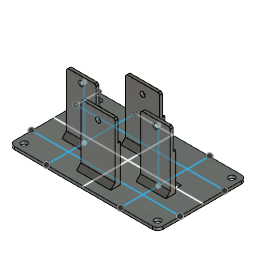
Chargers mount (Autodesk Fusion 360 design; units mm, degrees)
Autodesk Fusion 360 part; units mm, degrees
sketch "Sketch1" plane through (0, 0, 0) normal (0, 0, 1) x (1, 0, 0)
  line L0 (0, 0) -> (100, 0)
  line L1 (100, 0) -> (100, 60)
  line L2 (100, 60) -> (0, 60)
  line L3 (0, 60) -> (0, 0)
  dimension "d1" = 100
  dimension "d2" = 60
  constraint horizontal L0
  constraint vertical L1
  constraint horizontal L2
  constraint vertical L3
  constraint coincident L0.start L3.end
  measures "d1" distance of L0.start L0.end
  measures "d2" distance of L0.start L2.end
extrude "Extrude1" add sketch "Sketch1" along normal blind 2
sketch "Sketch2" plane through (0, 0, 2) normal (0, 0, 1) x (-1, 0, 0)
  line L0 (0, -60) -> (0, 0)
  line L1 (0, 0) -> (-100, 0)
  line L2 (-100, 0) -> (-100, -60)
  line L3 (-100, -60) -> (0, -60)
  line L4 (-50, -60) -> (-50, 0)
  line L5 (0, -30) -> (-100, -30)
  line L6 (-95, -5) -> (-5, -5)
  line L7 (-5, -5) -> (-5, -55)
  line L8 (-5, -55) -> (-95, -55)
  line L9 (-95, -55) -> (-95, -5)
  line L10 (-95, -5) -> (-5, -55) construction
  line L11 (-5, -5) -> (-95, -55) construction
  circle A0 centre (-5, -55) radius 2.1
  circle A1 centre (-95, -55) radius 2.1
  circle A2 centre (-5, -5) radius 2.1
  circle A3 centre (-95, -5) radius 2.1
  point P0 (-50, -30)
  dimension "d5" = 4.2
  dimension "d6" = 4.2
  dimension "d7" = 4.2
  dimension "d8" = 4.2
  constraint midpoint L3 L4.start
  constraint perpendicular L3 L4
  constraint midpoint L0 L5.start
  constraint perpendicular L4 L5
  constraint horizontal L6
  constraint perpendicular L6 L7
  constraint parallel L6 L8
  constraint parallel L7 L9
  constraint coincident L10 P0
  constraint coincident L11 P0
  constraint midpoint L4 P0
  constraint coincident L7.end L8.start
  constraint coincident L8.end L9.start
  constraint coincident L6.end L7.start
  constraint coincident L6.start L9.end
  measures "d5" diameter of A0
  measures "d6" diameter of A1
  measures "d7" diameter of A2
  measures "d8" diameter of A3
extrude "Extrude2" cut sketch "Sketch2" against normal blind 2345 contours L6 L7 A2 | L6 L7 A2 | L7 L8 A0 | L7 L8 A0 | L8 L9 A1 | L8 L9 A1 | L6 L9 A3 | L6 L9 A3
sketch "Sketch3" plane through (0, 0, 2) normal (0, 0, 1) x (-1, 0, 0)
  circle A0 centre (-95, -55) radius 2.1
  circle A1 centre (-95, -5) radius 2.1
  circle A2 centre (-5, -55) radius 2.1
  circle A3 centre (-5, -5) radius 2.1
  line L0 (0, -60) -> (0, 0)
  line L1 (0, 0) -> (-100, 0)
  line L2 (-100, 0) -> (-100, -60)
  line L3 (-100, -60) -> (0, -60)
  line L4 (-50, -60) -> (-50, 0)
  line L5 (0, -30) -> (-100, -30)
  line L6 (0, -60) -> (0, -45)
  line L7 (0, -45) -> (-100, -45)
  line L8 (-100, -15) -> (0, -15)
  line L9 (-50, -60) -> (-25, -60)
  line L10 (-25, -60) -> (-25, 0)
  line L11 (-75, -60) -> (-75, 0)
  constraint midpoint L3 L4.start
  constraint midpoint L1 L4.end
  constraint midpoint L0 L5.start
  constraint midpoint L2 L5.end
  constraint coincident L0.start L3.end
  constraint coincident L0 L6.end
  constraint coincident L2 L7.end
  constraint perpendicular L2 L7
  constraint coincident L2 L8.start
  constraint coincident L0 L8.end
  constraint perpendicular L0 L8
  constraint coincident L3 L9.end
  constraint coincident L1 L10.end
  constraint perpendicular L1 L10
  constraint coincident L3 L11.start
  constraint coincident L1 L11.end
  constraint perpendicular L1 L11
sketch "Sketch4" plane through (0, 0, 2) normal (0, 0, 1) x (-1, 0, 0)
  line L0 (-32.5, -26.5) -> (-17.5, -26.5)
  line L1 (-17.5, -26.5) -> (-17.5, -33.5)
  line L2 (-17.5, -33.5) -> (-32.5, -33.5)
  line L3 (-32.5, -33.5) -> (-32.5, -26.5)
  line L4 (-32.5, -26.5) -> (-17.5, -33.5) construction
  line L5 (-17.5, -26.5) -> (-32.5, -33.5) construction
  line L6 (-82.5, -26.5) -> (-67.5, -26.5)
  line L7 (-67.5, -26.5) -> (-67.5, -33.5)
  line L8 (-67.5, -33.5) -> (-82.5, -33.5)
  line L9 (-82.5, -33.5) -> (-82.5, -26.5)
  line L10 (-82.5, -26.5) -> (-67.5, -33.5) construction
  line L11 (-67.5, -26.5) -> (-82.5, -33.5) construction
  point P0 (-25, -30)
  point P1 (-75, -30)
  dimension "d11" = 15
  dimension "d12" = 7
  dimension "d13" = 15
  dimension "d14" = 7
  constraint horizontal L0
  constraint perpendicular L0 L1
  constraint parallel L0 L2
  constraint parallel L1 L3
  constraint coincident L4 P0
  constraint coincident L5 P0
  constraint horizontal L6
  constraint perpendicular L6 L7
  constraint parallel L6 L8
  constraint parallel L7 L9
  constraint coincident L10 P1
  constraint coincident L11 P1
  measures "d11" distance of L1.end L2.end
  measures "d12" distance of L0.end L1.end
  measures "d13" distance of L7.end L8.end
  measures "d14" distance of L6.end L7.end
sketch "Sketch5" plane through (0, 0, 2) normal (0, 0, 1) x (-1, 0, 0)
  line L0 (-45, -13.2) -> (-55, -13.2)
  arc A0 (-55, -13.2) -> (-55, -16.8) centre (-55, -15) ccw
  line L1 (-55, -16.8) -> (-45, -16.8)
  arc A1 (-45, -16.8) -> (-45, -13.2) centre (-45, -15) ccw
  line L2 (-45, -15) -> (-55, -15) construction
  line L3 (-45, -43.2) -> (-55, -43.2)
  arc A2 (-55, -43.2) -> (-55, -46.8) centre (-55, -45) ccw
  line L4 (-55, -46.8) -> (-45, -46.8)
  arc A3 (-45, -46.8) -> (-45, -43.2) centre (-45, -45) ccw
  line L5 (-45, -45) -> (-55, -45) construction
  point P0 (-50, -15)
  point P1 (-50, -45)
  dimension "d15" = 5
  dimension "d16" = 3.6
  dimension "d17" = 5
  dimension "d18" = 3.6
  constraint tangent L0 A0
  constraint tangent A0 L1
  constraint parallel L0 L1
  constraint tangent L1 A1
  constraint tangent L0 A1
  constraint horizontal L2
  constraint midpoint L2 P0
  constraint tangent L3 A2
  constraint tangent A2 L4
  constraint parallel L3 L4
  constraint tangent L4 A3
  constraint tangent L3 A3
  constraint horizontal L5
  constraint midpoint L5 P1
  measures "d15" distance of A0.centre P0
  measures "d16" diameter of A0
  measures "d17" distance of A2.centre P1
  measures "d18" diameter of A2
extrude "Extrude3" cut sketch "Sketch4" sketch "Sketch5" against normal blind 346436 of sketch 2
sketch "Sketch6" plane through (0, 0, 0) normal (0, 0, -1) x (1, 0, 0)
  line L0 (0, 0) -> (0, -60)
  line L1 (0, -60) -> (100, -60)
  line L2 (100, -60) -> (100, 0)
  line L3 (100, 0) -> (0, 0)
  circle A0 centre (5, -5) radius 2.1
  circle A1 centre (5, -55) radius 2.1
  circle A2 centre (95, -5) radius 2.1
  circle A3 centre (95, -55) radius 2.1
  line L4 (45, -13.2) -> (55, -13.2)
  arc A4 (55, -16.8) -> (55, -13.2) centre (55, -15) ccw
  line L5 (55, -16.8) -> (45, -16.8)
  arc A5 (45, -13.2) -> (45, -16.8) centre (45, -15) ccw
  line L6 (67.5, -33.5) -> (67.5, -26.5)
  line L7 (67.5, -26.5) -> (82.5, -26.5)
  line L8 (82.5, -26.5) -> (82.5, -33.5)
  line L9 (82.5, -33.5) -> (67.5, -33.5)
  line L10 (17.5, -33.5) -> (17.5, -26.5)
  line L11 (17.5, -26.5) -> (32.5, -26.5)
  line L12 (32.5, -26.5) -> (32.5, -33.5)
  line L13 (32.5, -33.5) -> (17.5, -33.5)
  line L14 (45, -43.2) -> (55, -43.2)
  arc A6 (55, -46.8) -> (55, -43.2) centre (55, -45) ccw
  line L15 (55, -46.8) -> (45, -46.8)
  arc A7 (45, -43.2) -> (45, -46.8) centre (45, -45) ccw
  line L16 (75, -50) -> (25, -50) construction
  line L17 (25, -50) -> (25, -60) construction
  line L18 (25, -60) -> (75, -60) construction
  line L19 (75, -60) -> (75, -50) construction
  line L20 (57, -37) -> (43, -37) construction
  line L21 (43, -37) -> (43, -42) construction
  line L22 (43, -42) -> (57, -42) construction
  line L23 (57, -42) -> (57, -37) construction
  line L24 (57, -18) -> (43, -18) construction
  line L25 (43, -18) -> (43, -23) construction
  line L26 (43, -23) -> (57, -23) construction
  line L27 (57, -23) -> (57, -18) construction
  line L28 (83, -20) -> (67, -20) construction
  line L29 (67, -20) -> (67, -25) construction
  line L30 (67, -25) -> (83, -25) construction
  line L31 (83, -25) -> (83, -20) construction
  line L32 (33, -20) -> (17, -20) construction
  line L33 (17, -20) -> (17, -25) construction
  line L34 (17, -25) -> (33, -25) construction
  line L35 (33, -25) -> (33, -20) construction
  dimension "d21" = 5.76
  dimension "d23" = 4
  dimension "d24" = 0
  dimension "d25" = 4
  dimension "d26" = 0
  dimension "d27" = 4
  dimension "d28" = 0
  dimension "d29" = 4
  dimension "d30" = 0
  text T0 "Chargers" font "Arial" height 5.76 align centre middle in box 50 x 10 at (75, -50) x (-1, 0) y (0, -1) spacing 1 kerned
  text T1 "65 W" font "Arial" height 4 align centre middle in box 14 x 5 at (57, -37) x (-1, 0) y (0, -1) spacing 1 kerned
  text T2 "65 W" font "Arial" height 4 align centre middle in box 14 x 5 at (57, -18) x (-1, 0) y (0, -1) spacing 1 kerned
  text T3 "24 W" font "Arial" height 4 align centre middle in box 16 x 5 at (83, -20) x (-1, 0) y (0, -1) spacing 1 kerned
  text T4 "24 W" font "Arial" height 4 align centre middle in box 16 x 5 at (33, -20) x (-1, 0) y (0, -1) spacing 1 kerned
  constraint coincident L1
extrude "Extrude4" cut sketch "Sketch6" against normal blind 0.5 text T0 T1 T3 T2 T4
sketch "Sketch7" plane through (0, 0, 2) normal (0, 0, 1) x (-1, 0, 0)
  line L0 (-45, -43) -> (-55, -43)
  arc A0 (-55, -43) -> (-55, -47) centre (-55, -45) ccw
  line L1 (-55, -47) -> (-45, -47)
  arc A1 (-45, -47) -> (-45, -43) centre (-45, -45) ccw
  line L2 (-45, -45) -> (-55, -45) construction
  line L3 (-45, -13) -> (-55, -13)
  arc A2 (-55, -13) -> (-55, -17) centre (-55, -15) ccw
  line L4 (-55, -17) -> (-45, -17)
  arc A3 (-45, -17) -> (-45, -13) centre (-45, -15) ccw
  line L5 (-45, -15) -> (-55, -15) construction
  point P0 (-50, -45)
  point P1 (-50, -15)
  dimension "d33" = 4
  dimension "d34" = 5
  dimension "d35" = 4
  constraint tangent L0 A0
  constraint tangent A0 L1
  constraint parallel L0 L1
  constraint tangent L1 A1
  constraint tangent L0 A1
  constraint horizontal L2
  constraint midpoint L2 P0
  constraint tangent L3 A2
  constraint tangent A2 L4
  constraint parallel L3 L4
  constraint tangent L4 A3
  constraint tangent L3 A3
  constraint parallel L2 L5
  constraint midpoint L5 P1
  measures "d33" diameter of A0
  measures "d34" distance of A2.centre P1
  measures "d35" diameter of A2
extrude "Extrude5" cut sketch "Sketch7" against normal blind 6543
sketch "Sketch8" plane through (0, 0, 2) normal (0, 0, 1) x (-1, 0, 0)
  line L0 (-50, -43) -> (-50, -42.4)
  line L1 (-60.5, -41.8) -> (-39.5, -41.8)
  line L2 (-39.5, -41.8) -> (-39.5, -43)
  line L3 (-39.5, -43) -> (-60.5, -43)
  line L4 (-60.5, -43) -> (-60.5, -41.8)
  line L5 (-60.5, -41.8) -> (-39.5, -43) construction
  line L6 (-39.5, -41.8) -> (-60.5, -43) construction
  line L7 (-50, -13) -> (-50, -12.4)
  line L8 (-60.5, -11.8) -> (-39.5, -11.8)
  line L9 (-39.5, -11.8) -> (-39.5, -13)
  line L10 (-39.5, -13) -> (-60.5, -13)
  line L11 (-60.5, -13) -> (-60.5, -11.8)
  line L12 (-60.5, -11.8) -> (-39.5, -13) construction
  line L13 (-39.5, -11.8) -> (-60.5, -13) construction
  line L14 (-25, -26.5) -> (-25, -26)
  line L15 (-34, -26.5) -> (-16, -26.5)
  line L16 (-16, -26.5) -> (-16, -25.5)
  line L17 (-16, -25.5) -> (-34, -25.5)
  line L18 (-34, -25.5) -> (-34, -26.5)
  line L19 (-34, -26.5) -> (-16, -25.5) construction
  line L20 (-16, -26.5) -> (-34, -25.5) construction
  line L21 (-75, -26.5) -> (-75, -26)
  line L22 (-84, -25.5) -> (-66, -25.5)
  line L23 (-66, -25.5) -> (-66, -26.5)
  line L24 (-66, -26.5) -> (-84, -26.5)
  line L25 (-84, -26.5) -> (-84, -25.5)
  line L26 (-84, -25.5) -> (-66, -26.5) construction
  line L27 (-66, -25.5) -> (-84, -26.5) construction
  point P0 (-50, -42.4)
  point P1 (-50, -12.4)
  point P2 (-25, -26)
  point P3 (-75, -26)
  dimension "d38" = 0.6
  dimension "d39" = 21
  dimension "d40" = 1.2
  dimension "d41" = 0.6
  dimension "d42" = 21
  dimension "d43" = 1.2
  dimension "d44" = 0.5
  dimension "d45" = 18
  dimension "d46" = 1
  dimension "d47" = 18
  dimension "d48" = 1
  constraint vertical L0
  constraint horizontal L1
  constraint perpendicular L1 L2
  constraint parallel L1 L3
  constraint parallel L2 L4
  constraint coincident L5 P0
  constraint coincident L6 P0
  constraint coincident P0 L0.end
  constraint vertical L7
  constraint horizontal L8
  constraint perpendicular L8 L9
  constraint parallel L8 L10
  constraint parallel L9 L11
  constraint coincident L12 P1
  constraint coincident L13 P1
  constraint coincident P1 L7.end
  constraint vertical L14
  constraint horizontal L15
  constraint perpendicular L15 L16
  constraint parallel L15 L17
  constraint parallel L16 L18
  constraint coincident L19 P2
  constraint coincident L20 P2
  constraint coincident P2 L14.end
  constraint vertical L21
  constraint horizontal L22
  constraint perpendicular L22 L23
  constraint parallel L22 L24
  constraint parallel L23 L25
  constraint coincident L26 P3
  constraint coincident L27 P3
  constraint coincident P3 L21.end
  measures "d38" distance of L0.start P0
  measures "d39" distance of L2.end L3.end
  measures "d40" distance of L1.end L2.end
  measures "d41" distance of L7.start P1
  measures "d42" distance of L9.end L10.end
  measures "d43" distance of L8.end L9.end
  measures "d44" distance of L14.start P2
  measures "d45" distance of L16.end L17.end
  measures "d46" distance of L15.end L16.end
  measures "d47" distance of L23.end L24.end
  measures "d48" distance of L22.end L23.end
extrude "Extrude6" cut sketch "Sketch8" against normal blind 0.9
sketch "Sketch9" plane through (0, 0, 2) normal (0, 0, 1) x (-1, 0, 0)
  line L0 (-50, -41.8) -> (-50, -40.8)
  line L1 (-50, -11.8) -> (-50, -10.8)
  line L2 (-25, -25.5) -> (-25, -24.5)
  line L3 (-75, -25.5) -> (-75, -24.5)
  line L4 (-61.5, -39.8) -> (-38.5, -39.8)
  line L5 (-38.5, -39.8) -> (-38.5, -41.8)
  line L6 (-38.5, -41.8) -> (-61.5, -41.8)
  line L7 (-61.5, -41.8) -> (-61.5, -39.8)
  line L8 (-61.5, -39.8) -> (-38.5, -41.8) construction
  line L9 (-38.5, -39.8) -> (-61.5, -41.8) construction
  line L10 (-61.5, -9.8) -> (-38.5, -9.8)
  line L11 (-38.5, -9.8) -> (-38.5, -11.8)
  line L12 (-38.5, -11.8) -> (-61.5, -11.8)
  line L13 (-61.5, -11.8) -> (-61.5, -9.8)
  line L14 (-61.5, -9.8) -> (-38.5, -11.8) construction
  line L15 (-38.5, -9.8) -> (-61.5, -11.8) construction
  line L16 (-35, -23.5) -> (-15, -23.5)
  line L17 (-15, -23.5) -> (-15, -25.5)
  line L18 (-15, -25.5) -> (-35, -25.5)
  line L19 (-35, -25.5) -> (-35, -23.5)
  line L20 (-35, -23.5) -> (-15, -25.5) construction
  line L21 (-15, -23.5) -> (-35, -25.5) construction
  line L22 (-85, -23.5) -> (-65, -23.5)
  line L23 (-65, -23.5) -> (-65, -25.5)
  line L24 (-65, -25.5) -> (-85, -25.5)
  line L25 (-85, -25.5) -> (-85, -23.5)
  line L26 (-85, -23.5) -> (-65, -25.5) construction
  line L27 (-65, -23.5) -> (-85, -25.5) construction
  point P0 (-50, -40.8)
  point P1 (-50, -10.8)
  point P2 (-25, -24.5)
  point P3 (-75, -24.5)
  dimension "d51" = 1
  dimension "d52" = 1
  dimension "d53" = 1
  dimension "d54" = 1
  dimension "d55" = 23
  dimension "d56" = 2
  dimension "d57" = 23
  dimension "d58" = 2
  dimension "d59" = 20
  dimension "d60" = 2
  dimension "d61" = 20
  dimension "d62" = 2
  constraint vertical L0
  constraint vertical L1
  constraint vertical L2
  constraint vertical L3
  constraint horizontal L4
  constraint perpendicular L4 L5
  constraint parallel L4 L6
  constraint parallel L5 L7
  constraint coincident L8 P0
  constraint coincident L9 P0
  constraint coincident P0 L0.end
  constraint horizontal L10
  constraint perpendicular L10 L11
  constraint parallel L10 L12
  constraint parallel L11 L13
  constraint coincident L14 P1
  constraint coincident L15 P1
  constraint coincident P1 L1.end
  constraint horizontal L16
  constraint perpendicular L16 L17
  constraint parallel L16 L18
  constraint parallel L17 L19
  constraint coincident L20 P2
  constraint coincident L21 P2
  constraint coincident P2 L2.end
  constraint horizontal L22
  constraint perpendicular L22 L23
  constraint parallel L22 L24
  constraint parallel L23 L25
  constraint coincident L26 P3
  constraint coincident L27 P3
  constraint coincident P3 L3.end
  measures "d51" distance of L0.start P0
  measures "d52" distance of L1.start P1
  measures "d53" distance of L2.start P2
  measures "d54" distance of L3.start P3
  measures "d55" distance of L5.end L6.end
  measures "d56" distance of L4.end L5.end
  measures "d57" distance of L11.end L12.end
  measures "d58" distance of L10.end L11.end
  measures "d59" distance of L17.end L18.end
  measures "d60" distance of L16.end L17.end
  measures "d61" distance of L23.end L24.end
  measures "d62" distance of L22.end L23.end
extrude "Extrude7" add sketch "Sketch9" along normal blind 55
chamfer "Chamfer1" distance 3 angle 45 1 edges at (50, 39.8, 2) tangent chain off
chamfer "Chamfer2" distance 3 angle 45 3 edges at (75, 23.5, 2) (25, 23.5, 2) (50, 9.8, 2) tangent chain off
sketch "Sketch10" plane through (0, 41.8, 0) normal (0, 1, 0) x (-1, 0, 0)
  line L0 (-60.5, 2) -> (-60.5, 1.1)
  line L1 (-60.5, 1.1) -> (-39.5, 1.1)
  line L2 (-39.5, 1.1) -> (-39.5, 2)
  line L3 (-39.5, 2) -> (-38.5, 2)
  line L4 (-38.5, 2) -> (-38.5, 57)
  line L5 (-38.5, 57) -> (-61.5, 57)
  line L6 (-61.5, 57) -> (-61.5, 2)
  line L7 (-61.5, 2) -> (-60.5, 2)
  line L8 (-38.5, 2) -> (-39.5, 2)
  line L9 (-39.5, 2) -> (-39.5, 27)
  line L10 (-39.5, 27) -> (-38.5, 27)
  line L11 (-38.5, 27) -> (-38.5, 2)
  line L12 (-61.5, 2) -> (-60.5, 2)
  line L13 (-60.5, 2) -> (-60.5, 27)
  line L14 (-60.5, 27) -> (-61.5, 27)
  line L15 (-61.5, 27) -> (-61.5, 2)
  dimension "d67" = 1
  dimension "d68" = 25
  dimension "d69" = 1
  dimension "d70" = 25
  constraint horizontal L8
  constraint vertical L9
  constraint horizontal L10
  constraint vertical L11
  constraint coincident L3.end L4.start
  constraint horizontal L12
  constraint vertical L13
  constraint horizontal L14
  constraint vertical L15
  constraint coincident L6.end L7.start
  measures "d67" distance of L3.end L2.end
  measures "d68" distance of L3.end L10.end
  measures "d69" distance of L6.end L0.start
  measures "d70" distance of L6.end L14.end
extrude "Extrude8" add sketch "Sketch10" along normal blind 1.6 contours L6 L7 L12 L13 L14 L15 | L3 L4 L8 L9 L10 L11
sketch "Sketch11" plane through (60.5, 0, 0) normal (-1, 0, 0) x (0, -1, 0)
  line L0 (-43, 2) -> (-43, 1.1)
  line L1 (-43, 1.1) -> (-41.8, 1.1)
  line L2 (-41.8, 1.1) -> (-41.8, 27)
  line L3 (-41.8, 27) -> (-43.4, 27)
  line L4 (-43.4, 27) -> (-43.4, 2)
  line L5 (-43.4, 2) -> (-43, 2)
  line L6 (-43.4, 2) -> (-43, 2)
  line L7 (-43, 2) -> (-43, 9)
  line L8 (-43, 9) -> (-43.4, 9)
  line L9 (-43.4, 9) -> (-43.4, 2)
  dimension "d73" = 0.4
  dimension "d74" = 7
  constraint horizontal L6
  constraint vertical L7
  constraint horizontal L8
  constraint vertical L9
  constraint coincident L4.end L5.start
  measures "d73" distance of L4.end L0.start
  measures "d74" distance of L4.end L8.end
extrude "Extrude9" add sketch "Sketch11" along normal blind 4 contours L4 L5 L6 L7 L8 L9
sketch "Sketch12" plane through (39.5, 0, 0) normal (1, 0, 0) x (0, 1, 0)
  line L0 (41.8, 27) -> (41.8, 1.1)
  line L1 (41.8, 1.1) -> (43, 1.1)
  line L2 (43, 1.1) -> (43, 2)
  line L3 (43, 2) -> (43.4, 2)
  line L4 (43.4, 2) -> (43.4, 27)
  line L5 (43.4, 27) -> (41.8, 27)
  line L6 (43.4, 2) -> (43, 2)
  line L7 (43, 2) -> (43, 9)
  line L8 (43, 9) -> (43.4, 9)
  line L9 (43.4, 9) -> (43.4, 2)
  dimension "d77" = 0.4
  dimension "d78" = 7
  constraint horizontal L6
  constraint vertical L7
  constraint horizontal L8
  constraint vertical L9
  constraint coincident L3.end L4.start
  measures "d77" distance of L3.end L2.end
  measures "d78" distance of L3.end L8.end
extrude "Extrude10" add sketch "Sketch12" along normal blind 3 contours L3 L4 L6 L7 L8 L9
extrude "Extrude11" add 1 faces at (42.5, 43.1333, 6.6667) along direction (1, 0, 0) blind 1
sketch "Sketch13" plane through (0, 11.8, 0) normal (0, 1, 0) x (-1, 0, 0)
  line L0 (-60.5, 2) -> (-60.5, 1.1)
  line L1 (-60.5, 1.1) -> (-39.5, 1.1)
  line L2 (-39.5, 1.1) -> (-39.5, 2)
  line L3 (-39.5, 2) -> (-38.5, 2)
  line L4 (-38.5, 2) -> (-38.5, 57)
  line L5 (-38.5, 57) -> (-61.5, 57)
  line L6 (-61.5, 57) -> (-61.5, 2)
  line L7 (-61.5, 2) -> (-60.5, 2)
  line L8 (-61.5, 2) -> (-60.5, 2)
  line L9 (-60.5, 2) -> (-60.5, 27)
  line L10 (-60.5, 27) -> (-61.5, 27)
  line L11 (-61.5, 27) -> (-61.5, 2)
  line L12 (-38.5, 2) -> (-39.5, 2)
  line L13 (-39.5, 2) -> (-39.5, 27)
  line L14 (-39.5, 27) -> (-38.5, 27)
  line L15 (-38.5, 27) -> (-38.5, 2)
  constraint horizontal L8
  constraint vertical L9
  constraint horizontal L10
  constraint vertical L11
  constraint coincident L6.end L7.start
  constraint horizontal L12
  constraint vertical L13
  constraint horizontal L14
  constraint vertical L15
  constraint coincident L3.end L4.start
extrude "Extrude12" add sketch "Sketch13" along normal blind 1.6 contours L6 L7 L8 L9 L10 L11 | L3 L4 L12 L13 L14 L15
sketch "Sketch14" plane through (39.5, 0, 0) normal (1, 0, 0) x (0, 1, 0)
  line L0 (11.8, 27) -> (11.8, 1.1)
  line L1 (11.8, 1.1) -> (13, 1.1)
  line L2 (13, 1.1) -> (13, 2)
  line L3 (13, 2) -> (13.4, 2)
  line L4 (13.4, 2) -> (13.4, 27)
  line L5 (13.4, 27) -> (11.8, 27)
  line L6 (13.4, 2) -> (13, 2)
  line L7 (13, 2) -> (13, 9)
  line L8 (13, 9) -> (13.4, 9)
  line L9 (13.4, 9) -> (13.4, 2)
  dimension "d85" = 0.4
  dimension "d86" = 7
  constraint horizontal L6
  constraint vertical L7
  constraint horizontal L8
  constraint vertical L9
  constraint coincident L3.end L4.start
  measures "d85" distance of L3.end L2.end
  measures "d86" distance of L3.end L8.end
sketch "Sketch15" plane through (60.5, 0, 0) normal (-1, 0, 0) x (0, -1, 0)
  line L0 (-13, 2) -> (-13, 1.1)
  line L1 (-13, 1.1) -> (-11.8, 1.1)
  line L2 (-11.8, 1.1) -> (-11.8, 27)
  line L3 (-11.8, 27) -> (-13.4, 27)
  line L4 (-13.4, 27) -> (-13.4, 2)
  line L5 (-13.4, 2) -> (-13, 2)
  line L6 (-13.4, 2) -> (-13, 2)
  line L7 (-13, 2) -> (-13, 9)
  line L8 (-13, 9) -> (-13.4, 9)
  line L9 (-13.4, 9) -> (-13.4, 2)
  constraint horizontal L6
  constraint vertical L7
  constraint horizontal L8
  constraint vertical L9
  constraint coincident L4.end L5.start
extrude "Extrude13" add sketch "Sketch15" along normal blind 4 contours L4 L5 L6 L7 L8 L9
extrude "Extrude14" add sketch "Sketch14" along normal blind 4 contours L3 L4 L6 L7 L8 L9
extrude "Extrude15" cut 4 faces at (53.8333, 41.1333, 57) (28.3333, 24.1667, 57) (53.8333, 11.1333, 57) (78.3333, 24.1667, 57) along direction (0, 0, -1) blind 20
sketch "Sketch16" plane through (0, 25.5, 0) normal (0, 1, 0) x (-1, 0, 0)
  line L0 (-15, 37) -> (-35, 37)
  line L1 (-35, 37) -> (-35, 2)
  line L2 (-35, 2) -> (-34, 2)
  line L3 (-34, 2) -> (-34, 1.1)
  line L4 (-34, 1.1) -> (-16, 1.1)
  line L5 (-16, 1.1) -> (-16, 2)
  line L6 (-16, 2) -> (-15, 2)
  line L7 (-15, 2) -> (-15, 37)
  line L8 (-15, 2) -> (-16, 2)
  line L9 (-16, 2) -> (-16, 27)
  line L10 (-16, 27) -> (-15, 27)
  line L11 (-15, 27) -> (-15, 2)
  line L12 (-35, 2) -> (-34, 2)
  line L13 (-34, 2) -> (-34, 27)
  line L14 (-34, 27) -> (-35, 27)
  line L15 (-35, 27) -> (-35, 2)
  line L16 (-65, 2) -> (-66, 2)
  line L17 (-66, 2) -> (-66, 27)
  line L18 (-66, 27) -> (-65, 27)
  line L19 (-65, 27) -> (-65, 2)
  line L20 (-85, 2) -> (-84, 2)
  line L21 (-84, 2) -> (-84, 27)
  line L22 (-84, 27) -> (-85, 27)
  line L23 (-85, 27) -> (-85, 2)
  dimension "d93" = 1
  dimension "d94" = 25
  dimension "d95" = 1
  dimension "d96" = 25
  dimension "d97" = 1
  dimension "d98" = 25
  dimension "d99" = 25
  constraint horizontal L8
  constraint vertical L9
  constraint horizontal L10
  constraint vertical L11
  constraint coincident L6.end L7.start
  constraint horizontal L12
  constraint vertical L13
  constraint horizontal L14
  constraint vertical L15
  constraint coincident L1.end L2.start
  constraint horizontal L16
  constraint vertical L17
  constraint horizontal L18
  constraint vertical L19
  constraint horizontal L20
  constraint vertical L21
  constraint horizontal L22
  constraint vertical L23
  measures "d93" distance of L6.end L5.end
  measures "d94" distance of L6.end L10.end
  measures "d95" distance of L1.end L2.end
  measures "d96" distance of L1.end L14.end
  measures "d97" distance of L16.start L16.end
  measures "d98" distance of L16.start L18.end
  measures "d99" distance of L20.start L22.end
extrude "Extrude16" add sketch "Sketch16" along normal blind 1.6 contours L6 L7 L8 L9 L10 L11 | L1 L2 L12 L13 L14 L15 | L16 L17 L18 L19 | L20 L21 L22 L23
sketch "Sketch17" plane through (84, 0, 0) normal (-1, 0, 0) x (0, -1, 0)
  line L0 (-26.5, 2) -> (-26.5, 1.1)
  line L1 (-26.5, 1.1) -> (-25.5, 1.1)
  line L2 (-25.5, 1.1) -> (-25.5, 27)
  line L3 (-25.5, 27) -> (-27.1, 27)
  line L4 (-27.1, 27) -> (-27.1, 2)
  line L5 (-27.1, 2) -> (-26.5, 2)
  line L6 (-27.1, 2) -> (-26.7, 2)
  line L7 (-26.7, 2) -> (-26.7, 12)
  line L8 (-26.7, 12) -> (-27.1, 12)
  line L9 (-27.1, 12) -> (-27.1, 2)
  dimension "d102" = 0.4
  dimension "d103" = 10
  constraint horizontal L6
  constraint vertical L7
  constraint horizontal L8
  constraint vertical L9
  constraint coincident L4.end L5.start
  measures "d102" distance of L4.end L6.end
  measures "d103" distance of L4.end L8.end
sketch "Sketch18" plane through (66, 0, 0) normal (1, 0, 0) x (0, 1, 0)
  line L0 (25.5, 27) -> (25.5, 1.1)
  line L1 (25.5, 1.1) -> (26.5, 1.1)
  line L2 (26.5, 1.1) -> (26.5, 2)
  line L3 (26.5, 2) -> (27.1, 2)
  line L4 (27.1, 2) -> (27.1, 27)
  line L5 (27.1, 27) -> (25.5, 27)
  line L6 (27.1, 2) -> (26.7, 2)
  line L7 (26.7, 2) -> (26.7, 12)
  line L8 (26.7, 12) -> (27.1, 12)
  line L9 (27.1, 12) -> (27.1, 2)
  constraint horizontal L6
  constraint vertical L7
  constraint horizontal L8
  constraint vertical L9
  constraint coincident L3.end L4.start
extrude "Extrude17" add sketch "Sketch18" along normal blind 1 contours L3 L4 L6 L7 L8 L9
extrude "Extrude18" add sketch "Sketch17" along normal blind 1 contours L4 L5 L6 L7 L8 L9
sketch "Sketch19" plane through (34, 0, 0) normal (-1, 0, 0) x (0, -1, 0)
  line L0 (-26.5, 2) -> (-26.5, 1.1)
  line L1 (-26.5, 1.1) -> (-25.5, 1.1)
  line L2 (-25.5, 1.1) -> (-25.5, 27)
  line L3 (-25.5, 27) -> (-27.1, 27)
  line L4 (-27.1, 27) -> (-27.1, 2)
  line L5 (-27.1, 2) -> (-26.5, 2)
  line L6 (-27.1, 2) -> (-26.7, 2)
  line L7 (-26.7, 2) -> (-26.7, 12)
  line L8 (-26.7, 12) -> (-27.1, 12)
  line L9 (-27.1, 12) -> (-27.1, 2)
  dimension "d108" = 0.4
  dimension "d109" = 10
  constraint horizontal L6
  constraint vertical L7
  constraint horizontal L8
  constraint vertical L9
  constraint coincident L4.end L5.start
  measures "d108" distance of L4.end L6.end
  measures "d109" distance of L4.end L8.end
sketch "Sketch20" plane through (16, 0, 0) normal (1, 0, 0) x (0, 1, 0)
  line L0 (25.5, 27) -> (25.5, 1.1)
  line L1 (25.5, 1.1) -> (26.5, 1.1)
  line L2 (26.5, 1.1) -> (26.5, 2)
  line L3 (26.5, 2) -> (27.1, 2)
  line L4 (27.1, 2) -> (27.1, 27)
  line L5 (27.1, 27) -> (25.5, 27)
  line L6 (27.1, 2) -> (26.7, 2)
  line L7 (26.7, 2) -> (26.7, 12)
  line L8 (26.7, 12) -> (27.1, 12)
  line L9 (27.1, 12) -> (27.1, 2)
  constraint horizontal L6
  constraint vertical L7
  constraint horizontal L8
  constraint vertical L9
  constraint coincident L3.end L4.start
extrude "Extrude19" add sketch "Sketch19" along normal blind 1 contours L4 L5 L6 L7 L8 L9
extrude "Extrude20" add sketch "Sketch20" along normal blind 1 contours L3 L4 L6 L7 L8 L9
sketch "Sketch21" plane through (0, 25.5, 0) normal (0, 1, 0) x (-1, 0, 0)
  line L0 (-34, 27) -> (-34, 1.1)
  line L1 (-34, 1.1) -> (-16, 1.1)
  line L2 (-16, 1.1) -> (-16, 27)
  line L3 (-16, 27) -> (-15, 27)
  line L4 (-15, 27) -> (-15, 37)
  line L5 (-15, 37) -> (-35, 37)
  line L6 (-35, 37) -> (-35, 27)
  line L7 (-35, 27) -> (-34, 27)
extrude "Extrude21" add 4 faces at (78.3333, 24.1667, 37) (53.8333, 11.1333, 37) (28.3333, 24.1667, 37) (53.8333, 41.1333, 37) along direction (0, 0, 1) blind 5
sketch "Sketch22" plane through (0, 25.5, 0) normal (0, 1, 0) x (-1, 0, 0)
  line L0 (-84, 27) -> (-84, 1.1)
  line L1 (-84, 1.1) -> (-66, 1.1)
  line L2 (-66, 1.1) -> (-66, 27)
  line L3 (-66, 27) -> (-65, 27)
  line L4 (-65, 27) -> (-65, 42)
  line L5 (-65, 42) -> (-85, 42)
  line L6 (-85, 42) -> (-85, 27)
  line L7 (-85, 27) -> (-84, 27)
  line L8 (-75, 2) -> (-75, 35.2)
  line L9 (-25, 2) -> (-25, 35.2)
  line L10 (-75, 35.2) -> (-75, 36.9)
  line L11 (-25, 35.2) -> (-25, 36.9)
  circle A0 centre (-75, 36.9) radius 1.7
  circle A1 centre (-25, 36.9) radius 1.7
  dimension "d116" = 33.2
  dimension "d117" = 33.2
  dimension "d118" = 1.7
  dimension "d119" = 1.7
  dimension "d120" = 3.4
  dimension "d121" = 3.4
  constraint perpendicular L1 L8
  constraint vertical L9
  constraint parallel L8 L10
  constraint parallel L9 L11
  constraint coincident L10.end A0.centre
  constraint coincident L11.end A1.centre
  measures "d116" distance of L8.start L8.end
  measures "d117" distance of L9.start L9.end
  measures "d118" distance of L8.end L10.end
  measures "d119" distance of L9.end L11.end
  measures "d120" diameter of A0
  measures "d121" diameter of A1
extrude "Extrude22" cut sketch "Sketch22" against normal blind 2345 contours A0 | A1
sketch "Sketch23" plane through (0, 41.8, 0) normal (0, 1, 0) x (-1, 0, 0)
  line L0 (-61.5, 42) -> (-61.5, 27)
  line L1 (-61.5, 27) -> (-60.5, 27)
  line L2 (-60.5, 27) -> (-60.5, 1.1)
  line L3 (-60.5, 1.1) -> (-39.5, 1.1)
  line L4 (-39.5, 1.1) -> (-39.5, 27)
  line L5 (-39.5, 27) -> (-38.5, 27)
  line L6 (-38.5, 27) -> (-38.5, 42)
  line L7 (-38.5, 42) -> (-61.5, 42)
  line L8 (-50, 2) -> (-50, 33.2)
  line L9 (-50, 33.2) -> (-50, 35.7)
  circle A0 centre (-50, 35.7) radius 1.7
  dimension "d124" = 31.2
  dimension "d125" = 2.5
  dimension "d126" = 3.4
  constraint perpendicular L3 L8
  constraint parallel L8 L9
  constraint coincident L9.end A0.centre
  measures "d124" distance of L8.start L8.end
  measures "d125" distance of L8.end L9.end
  measures "d126" diameter of A0
extrude "Extrude23" cut sketch "Sketch23" against normal blind 43634645 contours A0
sketch "Sketch24" plane through (0, 25.5, 0) normal (0, 1, 0) x (-1, 0, 0)
  circle A0 centre (-75, 36.9) radius 1.7
  line L0 (-84, 27) -> (-84, 1.1)
  line L1 (-84, 1.1) -> (-66, 1.1)
  line L2 (-66, 1.1) -> (-66, 27)
  line L3 (-66, 27) -> (-65, 27)
  line L4 (-65, 27) -> (-65, 42)
  line L5 (-65, 42) -> (-85, 42)
  line L6 (-85, 42) -> (-85, 27)
  line L7 (-85, 27) -> (-84, 27)
  circle A1 centre (-75, 36.9) radius 1.7
  circle A2 centre (-25, 36.9) radius 1.7
  constraint concentric A0 A1
extrude "Extrude24" add sketch "Sketch24" against normal blind 2 contours A0 A1 | A2
sketch "Sketch25" plane through (0, 25.5, 0) normal (0, 1, 0) x (-1, 0, 0)
  line L0 (-84, 27) -> (-84, 1.1)
  line L1 (-84, 1.1) -> (-66, 1.1)
  line L2 (-66, 1.1) -> (-66, 27)
  line L3 (-66, 27) -> (-65, 27)
  line L4 (-65, 27) -> (-65, 42)
  line L5 (-65, 42) -> (-85, 42)
  line L6 (-85, 42) -> (-85, 27)
  line L7 (-85, 27) -> (-84, 27)
  line L8 (-75, 2) -> (-75, 37.6)
  line L9 (-25, 2) -> (-25, 37.6)
  dimension "d131" = 35.6
  dimension "d133" = 35.6
  constraint perpendicular L1 L8
  constraint parallel L8 L9
  measures "d131" distance of L8.start L8.end
  measures "d133" distance of L9.start L9.end
sketch "Sketch26" plane through (0, 41.8, 0) normal (0, 1, 0) x (-1, 0, 0)
  circle A0 centre (-50, 35.7) radius 1.7
  line L0 (-61.5, 42) -> (-61.5, 27)
  line L1 (-61.5, 27) -> (-60.5, 27)
  line L2 (-60.5, 27) -> (-60.5, 1.1)
  line L3 (-60.5, 1.1) -> (-39.5, 1.1)
  line L4 (-39.5, 1.1) -> (-39.5, 27)
  line L5 (-39.5, 27) -> (-38.5, 27)
  line L6 (-38.5, 27) -> (-38.5, 42)
  line L7 (-38.5, 42) -> (-61.5, 42)
  circle A1 centre (-50, 35.7) radius 2.5
  line L8 (-75, 37.6) -> (-75, 37.7)
  circle A2 centre (-75, 37.7) radius 1.7
  line L9 (-25, 37.6) -> (-25, 37.7)
  circle A3 centre (-25, 37.7) radius 1.7
  dimension "d137" = 5
  dimension "d138" = 3.4
  dimension "d139" = 3.4
  constraint concentric A0 A1
  constraint vertical L8
  constraint coincident L8.end A2.centre
  constraint parallel L6 L9
  constraint coincident L9.end A3.centre
  measures "d137" diameter of A1
  measures "d138" diameter of A2
  measures "d139" diameter of A3
extrude "Extrude25" cut sketch "Sketch26" against normal blind 4646 contours A2 | A3
sketch "Sketch27" plane through (0, 25.5, 0) normal (0, 1, 0) x (-1, 0, 0)
chamfer "Chamfer3" distance 0.4 angle 45 16 edges at (75, 33.5, 0) (82.5, 30, 0) (67.5, 30, 0) (75, 26.5, 0) (25, 33.5, 0) (32.5, 30, 0) (25, 26.5, 0) (17.5, 30, 0) (57, 45, 0) (50, 47, 0) (43, 45, 0) (50, 43, 0) (50, 17, 0) (43, 15, 0) (50, 13, 0) (57, 15, 0) tangent chain off
chamfer "Chamfer4" distance 1 angle 45 8 edges at (84, 26.9, 12) (66, 26.9, 12) (60.5, 43.2, 9) (39.5, 43.2, 9) (34, 26.9, 12) (16, 26.9, 12) (39.5, 13.2, 9) (60.5, 13.2, 9) tangent chain off
chamfer "Chamfer5" distance 1 angle 45 8 edges at (85, 24.5, 42) (65, 24.5, 42) (61.5, 40.8, 42) (38.5, 40.8, 42) (15, 24.5, 42) (35, 24.5, 42) (38.5, 10.8, 42) (61.5, 10.8, 42) tangent chain off
fillet "Fillet1" radius 3.5 1 edges at (0, 60, 1)
fillet "Fillet2" radius 3.5 1 edges at (0, 0, 1)
fillet "Fillet3" radius 3.5 1 edges at (100, 0, 1)
fillet "Fillet4" radius 3.5 1 edges at (100, 60, 1)
equation "d22 = 'Chargers'"
equation "d24 = '65 W'"
equation "d26 = '65 W'"
equation "d28 = '24 W'"
equation "d30 = '24 W'"
equation "d116 = 34 mm - 0.8 mm"
equation "d124 = -0.8 mm + 32 mm"
equation "d131 = -0.9 mm + 34 mm + 2.5 mm"
